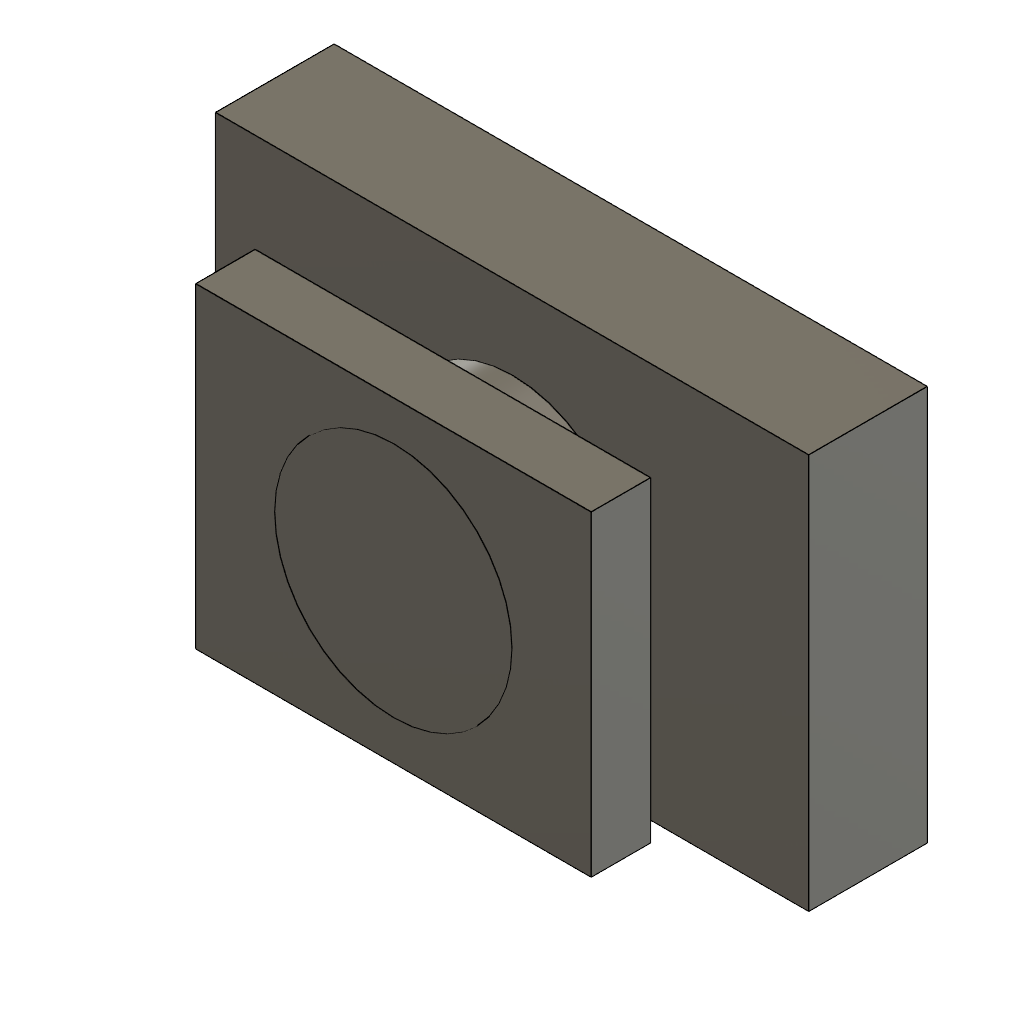
sk_intersect_plane (Autodesk Fusion 360 design; units mm, degrees)
part number: 2026-11-13-14-35-30-823
Autodesk Fusion 360 part; units mm, degrees
sketch "Sketch1" plane through (0, 0, 0) normal (0, 0, 1) x (1, 0, 0)
  line L0 (0, 0) -> (30, 0)
  line L1 (30, 0) -> (30, 20)
  line L2 (30, 20) -> (0, 20)
  line L3 (0, 20) -> (0, 0)
extrude "Extrude1" add sketch "Sketch1" along normal blind 6 makes body 1
sketch "Sketch2" plane through (0, 0, 0) normal (0, 0, 1) x (1, 0, 0)
  circle A0 centre (15, 10) radius 6
extrude "Extrude2" add sketch "Sketch2" along normal blind 12 bodies 1
ref_plane "WorkPlane1" through (0, 0, 9) normal (0, 0, 1) x (1, 0, 0)
sketch "Sketch3" plane through (0, 0, 9) normal (0, 0, 1) x (1, 0, 0)
  circle A0 centre (15, 10) radius 6
  line L0 (5, 2) -> (25, 2)
  line L1 (25, 2) -> (25, 18)
  line L2 (25, 18) -> (5, 18)
  line L3 (5, 18) -> (5, 2)
extrude "Extrude3" add sketch "Sketch3" along normal blind 3 separate body contours A0 | L0 L1 L2 L3 makes body 2
